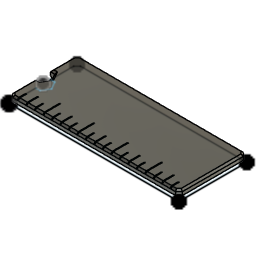
Magnetic Stud Finer v1 (Autodesk Fusion 360 design; units mm, degrees)
Autodesk Fusion 360 part; units mm, degrees
sketch "Sketch1" plane through (0, 0, 0) normal (0, 0, 1) x (1, 0, 0)
  line L0 (2.54, 0) -> (124.46, 0)
  line L1 (127, 2.54) -> (127, 48.26)
  line L2 (124.46, 50.8) -> (2.54, 50.8)
  line L3 (0, 48.26) -> (2.54, 50.8)
  line L4 (0, 2.54) -> (2.54, 0)
  line L5 (124.46, 50.8) -> (127, 48.26)
  line L6 (127, 2.54) -> (124.46, 0)
  line L7 (6.35, 25.4) -> (3.175, 30.8993)
  line L8 (3.175, 30.8993) -> (0, 30.8993)
  line L9 (0, 19.9007) -> (3.175, 19.9007)
  line L10 (3.175, 19.9007) -> (6.35, 25.4)
  line L11 (0, 48.26) -> (0, 30.8993)
  line L12 (0, 19.9007) -> (0, 2.54)
  point P0 (0.0687, -0.0333)
  point P1 (127, 0)
  point P2 (127, 50.8)
  point P3 (0, 50.8)
  point P4 (0, 25.4)
  dimension "d19" = 50.8
  dimension "d20" = 127
  dimension "d21" = 2.54
  dimension "d22" = 2.54
  dimension "d23" = 2.54
  dimension "d24" = 2.54
  dimension "d25" = 2.54
  dimension "d26" = 2.54
  dimension "d27" = 2.54
  dimension "d28" = 2.54
  dimension "d29" = 6.35
  constraint horizontal L0
  constraint vertical L1
  constraint horizontal L2
  constraint vertical L11
  constraint coincident P3 L11
  constraint coincident P3 L2
  constraint coincident origin L11
  constraint coincident origin L0
  constraint coincident P2 L2
  constraint coincident P2 L1
  constraint coincident P1 L1
  constraint coincident P1 L0
  constraint coincident L9.start L11
  constraint collinear L11 L12
  constraint coincident P4 L11
  measures "d19" distance of L0 L2
  measures "d20" distance of L1 L11
  measures "d21" distance of P3 L3.start
  measures "d22" distance of P3 L2.end
  measures "d23" distance of origin L4.start
  measures "d24" distance of origin L0.start
  measures "d25" distance of P2 L2.start
  measures "d26" distance of P2 L1.end
  measures "d27" distance of P1 L1.start
  measures "d28" distance of P1 L0.end
  measures "d29" distance of L7.start P4
extrude "Extrude2" add sketch "Sketch1" along normal blind 6.35
chamfer "Chamfer3" distance 2.54 angle 45 1 faces at (85.09, 25.4, 0)
chamfer "Chamfer4" distance 1.27 angle 45 1 faces at (85.09, 25.4, 6.35)
delete_face "DeleteFace11" 4 faces at (1.905, 31.7459, 1.6933) (6.7581, 28.0798, 0.8467) (6.7581, 22.7202, 0.8467) (1.905, 19.0541, 1.6933)
sketch "Sketch2" plane through (0, 0, 6.35) normal (0, 0, 1) x (-1, 0, 0)
  line L0 (-125.73, -47.7339) -> (-123.9339, -49.53)
  line L1 (-123.9339, -49.53) -> (-3.0661, -49.53)
  line L2 (-3.0661, -49.53) -> (-1.27, -47.7339)
  line L3 (-1.27, -47.7339) -> (-1.27, -32.1693)
  line L4 (-1.27, -32.1693) -> (-3.9082, -32.1693)
  line L5 (-3.9082, -32.1693) -> (-7.8165, -25.4)
  line L6 (-7.8165, -25.4) -> (-3.9082, -18.6307)
  line L7 (-3.9082, -18.6307) -> (-1.27, -18.6307)
  line L8 (-1.27, -18.6307) -> (-1.27, -3.0661)
  line L9 (-1.27, -3.0661) -> (-3.0661, -1.27)
  line L10 (-3.0661, -1.27) -> (-123.9339, -1.27)
  line L11 (-123.9339, -1.27) -> (-125.73, -3.0661)
  line L12 (-125.73, -3.0661) -> (-125.73, -47.7339)
  line L13 (0, -19.9007) -> (0, -2.54)
  line L14 (-25.4, 0) -> (-25.4, -12.7)
  line L15 (-50.8, 0) -> (-50.8, -12.7)
  line L16 (-76.2, 0) -> (-76.2, -12.7)
  line L17 (-101.6, 0) -> (-101.6, -12.7)
  line L18 (-25.7175, 0) -> (-25.0825, 0)
  line L19 (-25.0825, 0) -> (-25.0825, -12.7)
  line L20 (-25.0825, -12.7) -> (-25.7175, -12.7)
  line L21 (-25.7175, -12.7) -> (-25.7175, 0)
  line L22 (-25.7175, 0) -> (-25.0825, -12.7) construction
  line L23 (-25.0825, 0) -> (-25.7175, -12.7) construction
  line L24 (-51.1175, 0) -> (-50.4825, 0)
  line L25 (-50.4825, 0) -> (-50.4825, -12.7)
  line L26 (-50.4825, -12.7) -> (-51.1175, -12.7)
  line L27 (-51.1175, -12.7) -> (-51.1175, 0)
  line L28 (-51.1175, 0) -> (-50.4825, -12.7) construction
  line L29 (-50.4825, 0) -> (-51.1175, -12.7) construction
  line L30 (-76.5175, 0) -> (-75.8825, 0)
  line L31 (-75.8825, 0) -> (-75.8825, -12.7)
  line L32 (-75.8825, -12.7) -> (-76.5175, -12.7)
  line L33 (-76.5175, -12.7) -> (-76.5175, 0)
  line L34 (-76.5175, 0) -> (-75.8825, -12.7) construction
  line L35 (-75.8825, 0) -> (-76.5175, -12.7) construction
  line L36 (-101.9175, 0) -> (-101.2825, 0)
  line L37 (-101.2825, 0) -> (-101.2825, -12.7)
  line L38 (-101.2825, -12.7) -> (-101.9175, -12.7)
  line L39 (-101.9175, -12.7) -> (-101.9175, 0)
  line L40 (-101.9175, 0) -> (-101.2825, -12.7) construction
  line L41 (-101.2825, 0) -> (-101.9175, -12.7) construction
  line L42 (-12.7, 0) -> (-12.7, -8.89)
  line L43 (-38.1, 0) -> (-38.1, -8.89)
  line L44 (-63.5, 0) -> (-63.5, -8.89)
  line L45 (-88.9, 0) -> (-88.9, -8.89)
  line L46 (-114.3, 0) -> (-114.3, -8.89)
  line L47 (-6.35, 0) -> (-6.35, -6.35)
  line L48 (-19.05, 0) -> (-19.05, -6.35)
  line L49 (-31.75, 0) -> (-31.75, -6.35)
  line L50 (-44.45, 0) -> (-44.45, -6.35)
  line L51 (-57.15, 0) -> (-57.15, -6.35)
  line L52 (-69.85, 0) -> (-69.85, -6.35)
  line L53 (-82.55, 0) -> (-82.55, -6.35)
  line L54 (-95.25, 0) -> (-95.25, -6.35)
  line L55 (-107.95, 0) -> (-107.95, -6.35)
  line L56 (-120.65, 0) -> (-120.65, -6.35)
  line L57 (-6.6675, 0) -> (-6.0325, 0)
  line L58 (-6.0325, 0) -> (-6.0325, -6.35)
  line L59 (-6.0325, -6.35) -> (-6.6675, -6.35)
  line L60 (-6.6675, -6.35) -> (-6.6675, 0)
  line L61 (-6.6675, 0) -> (-6.0325, -6.35) construction
  line L62 (-6.0325, 0) -> (-6.6675, -6.35) construction
  line L63 (-13.0175, 0) -> (-12.3825, 0)
  line L64 (-12.3825, 0) -> (-12.3825, -8.89)
  line L65 (-12.3825, -8.89) -> (-13.0175, -8.89)
  line L66 (-13.0175, -8.89) -> (-13.0175, 0)
  line L67 (-13.0175, 0) -> (-12.3825, -8.89) construction
  line L68 (-12.3825, 0) -> (-13.0175, -8.89) construction
  line L69 (-19.3675, 0) -> (-18.7325, 0)
  line L70 (-18.7325, 0) -> (-18.7325, -6.35)
  line L71 (-18.7325, -6.35) -> (-19.3675, -6.35)
  line L72 (-19.3675, -6.35) -> (-19.3675, 0)
  line L73 (-19.3675, 0) -> (-18.7325, -6.35) construction
  line L74 (-18.7325, 0) -> (-19.3675, -6.35) construction
  line L75 (-32.0675, 0) -> (-31.4325, 0)
  line L76 (-31.4325, 0) -> (-31.4325, -6.35)
  line L77 (-31.4325, -6.35) -> (-32.0675, -6.35)
  line L78 (-32.0675, -6.35) -> (-32.0675, 0)
  line L79 (-32.0675, 0) -> (-31.4325, -6.35) construction
  line L80 (-31.4325, 0) -> (-32.0675, -6.35) construction
  line L81 (-38.4175, 0) -> (-37.7825, 0)
  line L82 (-37.7825, 0) -> (-37.7825, -8.89)
  line L83 (-37.7825, -8.89) -> (-38.4175, -8.89)
  line L84 (-38.4175, -8.89) -> (-38.4175, 0)
  line L85 (-38.4175, 0) -> (-37.7825, -8.89) construction
  line L86 (-37.7825, 0) -> (-38.4175, -8.89) construction
  line L87 (-44.7675, 0) -> (-44.1325, 0)
  line L88 (-44.1325, 0) -> (-44.1325, -6.35)
  line L89 (-44.1325, -6.35) -> (-44.7675, -6.35)
  line L90 (-44.7675, -6.35) -> (-44.7675, 0)
  line L91 (-44.7675, 0) -> (-44.1325, -6.35) construction
  line L92 (-44.1325, 0) -> (-44.7675, -6.35) construction
  line L93 (-57.4675, 0) -> (-56.8325, 0)
  line L94 (-56.8325, 0) -> (-56.8325, -6.35)
  line L95 (-56.8325, -6.35) -> (-57.4675, -6.35)
  line L96 (-57.4675, -6.35) -> (-57.4675, 0)
  line L97 (-57.4675, 0) -> (-56.8325, -6.35) construction
  line L98 (-56.8325, 0) -> (-57.4675, -6.35) construction
  line L99 (-63.8175, 0) -> (-63.1825, 0)
  line L100 (-63.1825, 0) -> (-63.1825, -8.89)
  line L101 (-63.1825, -8.89) -> (-63.8175, -8.89)
  line L102 (-63.8175, -8.89) -> (-63.8175, 0)
  line L103 (-63.8175, 0) -> (-63.1825, -8.89) construction
  line L104 (-63.1825, 0) -> (-63.8175, -8.89) construction
  line L105 (-70.1675, 0) -> (-69.5325, 0)
  line L106 (-69.5325, 0) -> (-69.5325, -6.35)
  line L107 (-69.5325, -6.35) -> (-70.1675, -6.35)
  line L108 (-70.1675, -6.35) -> (-70.1675, 0)
  line L109 (-70.1675, 0) -> (-69.5325, -6.35) construction
  line L110 (-69.5325, 0) -> (-70.1675, -6.35) construction
  line L111 (-82.8675, 0) -> (-82.2325, 0)
  line L112 (-82.2325, 0) -> (-82.2325, -6.35)
  line L113 (-82.2325, -6.35) -> (-82.8675, -6.35)
  line L114 (-82.8675, -6.35) -> (-82.8675, 0)
  line L115 (-82.8675, 0) -> (-82.2325, -6.35) construction
  line L116 (-82.2325, 0) -> (-82.8675, -6.35) construction
  line L117 (-89.2175, 0) -> (-88.5825, 0)
  line L118 (-88.5825, 0) -> (-88.5825, -8.89)
  line L119 (-88.5825, -8.89) -> (-89.2175, -8.89)
  line L120 (-89.2175, -8.89) -> (-89.2175, 0)
  line L121 (-89.2175, 0) -> (-88.5825, -8.89) construction
  line L122 (-88.5825, 0) -> (-89.2175, -8.89) construction
  line L123 (-95.5675, 0) -> (-94.9325, 0)
  line L124 (-94.9325, 0) -> (-94.9325, -6.35)
  line L125 (-94.9325, -6.35) -> (-95.5675, -6.35)
  line L126 (-95.5675, -6.35) -> (-95.5675, 0)
  line L127 (-95.5675, 0) -> (-94.9325, -6.35) construction
  line L128 (-94.9325, 0) -> (-95.5675, -6.35) construction
  line L129 (-108.2675, 0) -> (-107.6325, 0)
  line L130 (-107.6325, 0) -> (-107.6325, -6.35)
  line L131 (-107.6325, -6.35) -> (-108.2675, -6.35)
  line L132 (-108.2675, -6.35) -> (-108.2675, 0)
  line L133 (-108.2675, 0) -> (-107.6325, -6.35) construction
  line L134 (-107.6325, 0) -> (-108.2675, -6.35) construction
  line L135 (-114.6175, 0) -> (-113.9825, 0)
  line L136 (-113.9825, 0) -> (-113.9825, -8.89)
  line L137 (-113.9825, -8.89) -> (-114.6175, -8.89)
  line L138 (-114.6175, -8.89) -> (-114.6175, 0)
  line L139 (-114.6175, 0) -> (-113.9825, -8.89) construction
  line L140 (-113.9825, 0) -> (-114.6175, -8.89) construction
  line L141 (-120.9675, 0) -> (-120.3325, 0)
  line L142 (-120.3325, 0) -> (-120.3325, -6.35)
  line L143 (-120.3325, -6.35) -> (-120.9675, -6.35)
  line L144 (-120.9675, -6.35) -> (-120.9675, 0)
  line L145 (-120.9675, 0) -> (-120.3325, -6.35) construction
  line L146 (-120.3325, 0) -> (-120.9675, -6.35) construction
  arc A0 (-127, 0) -> (0, 0) centre (-63.5, 66.675) ccw
  point P0 (-25.4, -6.35)
  point P1 (-50.8, -6.35)
  point P2 (-76.2, -6.35)
  point P3 (-101.6, -6.35)
  point P4 (-6.35, -3.175)
  point P5 (-12.7, -4.445)
  point P6 (-19.05, -3.175)
  point P7 (-31.75, -3.175)
  point P8 (-38.1, -4.445)
  point P9 (-44.45, -3.175)
  point P10 (-57.15, -3.175)
  point P11 (-63.5, -4.445)
  point P12 (-69.85, -3.175)
  point P13 (-82.55, -3.175)
  point P14 (-88.9, -4.445)
  point P15 (-95.25, -3.175)
  point P16 (-107.95, -3.175)
  point P17 (-114.3, -4.445)
  point P18 (-120.65, -3.175)
  dimension "d43" = 12.7
  dimension "d44" = 12.7
  dimension "d45" = 25.4
  dimension "d46" = 12.7
  dimension "d47" = 25.4
  dimension "d48" = 25.4
  dimension "d49" = 0.635
  dimension "d50" = 0.635
  dimension "d51" = 0.635
  dimension "d52" = 0.635
  dimension "d55" = 8.89
  dimension "d56" = 8.89
  dimension "d57" = 25.4
  dimension "d58" = 8.89
  dimension "d59" = 25.4
  dimension "d60" = 8.89
  dimension "d61" = 25.4
  dimension "d62" = 8.89
  dimension "d63" = 25.4
  dimension "d64" = 6.35
  dimension "d65" = 12.7
  dimension "d66" = 6.35
  dimension "d67" = 6.35
  dimension "d68" = 6.35
  dimension "d69" = 6.35
  dimension "d70" = 6.35
  dimension "d71" = 6.35
  dimension "d72" = 6.35
  dimension "d73" = 6.35
  dimension "d74" = 6.35
  dimension "d75" = 6.35
  dimension "d76" = 6.35
  dimension "d77" = 12.7
  dimension "d79" = 0.635
  dimension "d80" = 0.635
  dimension "d81" = 0.635
  dimension "d82" = 0.635
  dimension "d83" = 0.635
  dimension "d84" = 0.635
  dimension "d85" = 0.635
  dimension "d86" = 0.635
  dimension "d87" = 0.635
  dimension "d88" = 0.635
  dimension "d89" = 0.635
  dimension "d90" = 0.635
  dimension "d91" = 0.635
  dimension "d92" = 0.635
  dimension "d93" = 0.635
  dimension "d96" = 10.0076
  constraint horizontal L18
  constraint perpendicular L18 L19
  constraint parallel L18 L20
  constraint parallel L19 L21
  constraint coincident L22 P0
  constraint coincident L23 P0
  constraint midpoint L14 P0
  constraint horizontal L24
  constraint perpendicular L24 L25
  constraint parallel L24 L26
  constraint parallel L25 L27
  constraint coincident L28 P1
  constraint coincident L29 P1
  constraint midpoint L15 P1
  constraint horizontal L30
  constraint perpendicular L30 L31
  constraint parallel L30 L32
  constraint parallel L31 L33
  constraint coincident L34 P2
  constraint coincident L35 P2
  constraint midpoint L16 P2
  constraint horizontal L36
  constraint perpendicular L36 L37
  constraint parallel L36 L38
  constraint parallel L37 L39
  constraint coincident L40 P3
  constraint coincident L41 P3
  constraint midpoint L17 P3
  constraint perpendicular L10 L42
  constraint perpendicular L10 L44
  constraint perpendicular L10 L46
  constraint perpendicular L10 L48
  constraint perpendicular L10 L50
  constraint perpendicular L10 L53
  constraint perpendicular L10 L54
  constraint perpendicular L10 L55
  constraint horizontal L57
  constraint perpendicular L57 L58
  constraint parallel L57 L59
  constraint parallel L58 L60
  constraint coincident L61 P4
  constraint coincident L62 P4
  constraint midpoint L47 P4
  constraint horizontal L63
  constraint perpendicular L63 L64
  constraint parallel L63 L65
  constraint parallel L64 L66
  constraint coincident L67 P5
  constraint coincident L68 P5
  constraint midpoint L42 P5
  constraint horizontal L69
  constraint perpendicular L69 L70
  constraint parallel L69 L71
  constraint parallel L70 L72
  constraint coincident L73 P6
  constraint coincident L74 P6
  constraint midpoint L48 P6
  constraint horizontal L75
  constraint perpendicular L75 L76
  constraint parallel L75 L77
  constraint parallel L76 L78
  constraint coincident L79 P7
  constraint coincident L80 P7
  constraint midpoint L49 P7
  constraint horizontal L81
  constraint perpendicular L81 L82
  constraint parallel L81 L83
  constraint parallel L82 L84
  constraint coincident L85 P8
  constraint coincident L86 P8
  constraint midpoint L43 P8
  constraint horizontal L87
  constraint perpendicular L87 L88
  constraint parallel L87 L89
  constraint parallel L88 L90
  constraint coincident L91 P9
  constraint coincident L92 P9
  constraint midpoint L50 P9
  constraint horizontal L93
  constraint perpendicular L93 L94
  constraint parallel L93 L95
  constraint parallel L94 L96
  constraint coincident L97 P10
  constraint coincident L98 P10
  constraint midpoint L51 P10
  constraint horizontal L99
  constraint perpendicular L99 L100
  constraint parallel L99 L101
  constraint parallel L100 L102
  constraint coincident L103 P11
  constraint coincident L104 P11
  constraint midpoint L44 P11
  constraint horizontal L105
  constraint perpendicular L105 L106
  constraint parallel L105 L107
  constraint parallel L106 L108
  constraint coincident L109 P12
  constraint coincident L110 P12
  constraint midpoint L52 P12
  constraint horizontal L111
  constraint perpendicular L111 L112
  constraint parallel L111 L113
  constraint parallel L112 L114
  constraint coincident L115 P13
  constraint coincident L116 P13
  constraint midpoint L53 P13
  constraint horizontal L117
  constraint perpendicular L117 L118
  constraint parallel L117 L119
  constraint parallel L118 L120
  constraint coincident L121 P14
  constraint coincident L122 P14
  constraint midpoint L45 P14
  constraint horizontal L123
  constraint perpendicular L123 L124
  constraint parallel L123 L125
  constraint parallel L124 L126
  constraint coincident L127 P15
  constraint coincident L128 P15
  constraint midpoint L54 P15
  constraint horizontal L129
  constraint perpendicular L129 L130
  constraint parallel L129 L131
  constraint parallel L130 L132
  constraint coincident L133 P16
  constraint coincident L134 P16
  constraint midpoint L55 P16
  constraint horizontal L135
  constraint perpendicular L135 L136
  constraint parallel L135 L137
  constraint parallel L136 L138
  constraint coincident L139 P17
  constraint coincident L140 P17
  constraint midpoint L46 P17
  constraint horizontal L141
  constraint perpendicular L141 L142
  constraint parallel L141 L143
  constraint parallel L142 L144
  constraint coincident L145 P18
  constraint coincident L146 P18
  constraint midpoint L56 P18
  constraint coincident A0.end origin
  measures "d43" distance of L14.start L14.end
  measures "d44" distance of L15.start L15.end
  measures "d45" distance of L14 L15
  measures "d46" distance of L16.start L16.end
  measures "d47" distance of L15 L16
  measures "d48" distance of L16 L17
  measures "d49" distance of L19.end L20.end
  measures "d50" distance of L25.end L26.end
  measures "d51" distance of L31.end L32.end
  measures "d52" distance of L37.end L38.end
  measures "d55" distance of L42.start L42.end
  measures "d56" distance of L43.start L43.end
  measures "d57" distance of L42 L43
  measures "d58" distance of L44.start L44.end
  measures "d59" distance of L43 L44
  measures "d60" distance of L45.start L45.end
  measures "d61" distance of L44 L45
  measures "d62" distance of L46.start L46.end
  measures "d63" distance of L45 L46
  measures "d64" distance of L48.start L48.end
  measures "d65" distance of L47 L48
  measures "d66" distance of L49.start L49.end
  measures "d67" distance of L43 L49
  measures "d68" distance of L50.start L50.end
  measures "d69" distance of L51.start L51.end
  measures "d70" distance of L52.start L52.end
  measures "d71" distance of L53.start L53.end
  measures "d72" distance of L16 L53
  measures "d73" distance of L54.start L54.end
  measures "d74" distance of L45 L54
  measures "d75" distance of L55.start L55.end
  measures "d76" distance of L56.start L56.end
  measures "d77" distance of L55 L56
  measures "d79" distance of L58.end L59.end
  measures "d80" distance of L64.end L65.end
  measures "d81" distance of L70.end L71.end
  measures "d82" distance of L76.end L77.end
  measures "d83" distance of L82.end L83.end
  measures "d84" distance of L88.end L89.end
  measures "d85" distance of L94.end L95.end
  measures "d86" distance of L100.end L101.end
  measures "d87" distance of L106.end L107.end
  measures "d88" distance of L112.end L113.end
  measures "d89" distance of L118.end L119.end
  measures "d90" distance of L124.end L125.end
  measures "d91" distance of L130.end L131.end
  measures "d92" distance of L136.end L137.end
  measures "d93" distance of L142.end L143.end
extrude "Extrude3" cut sketch "Sketch2" against normal blind 1.27 contours L10 L17 L36 L39 | L10 L17 L38 L39 | L10 L17 L36 L37 | L10 L17 L37 L38 | L10 L14 L19 L20 | L10 L14 L18 L19 | L10 L14 L20 L21 | L10 L14 L18 L21 | L10 L16 L30 L33 | L10 L16 L32 L33 | L10 L16 L30 L31 | L10 L16 L31 L32 | L10 L15 L25 L26 | L10 L15 L24 L25 | L10 L15 L26 L27 | L10 L15 L24 L27
extrude "Extrude4" cut sketch "Sketch2" against normal blind 1.27 contours L56 L143 L144 A0 | L10 L56 L144 A0 | L10 L56 L141 L144 | L56 L142 L143 A0 | L10 L56 L142 A0 | L10 L56 L141 L142 | L47 L59 L60 A0 | L10 L47 L60 A0 | L10 L46 L135 L138 | L10 L46 L137 L138 | L10 L47 L57 L60 | L47 L58 L59 A0 | L10 L47 L58 A0 | L10 L46 L135 L136 | L10 L46 L136 L137 | L10 L47 L57 L58 | L10 L42 L64 L65 | L10 L42 L63 L64 | L10 L42 L65 L66 | L10 L42 L63 L66 | L10 L55 L129 L132 | L10 L55 L131 L132 | L10 L55 L129 L130 | L10 L55 L130 L131 | L10 L48 L70 L71 | L10 L48 L69 L70 | L10 L48 L71 L72 | L10 L48 L69 L72 | L10 L54 L123 L126 | L10 L54 L125 L126 | L10 L54 L123 L124 | L10 L54 L124 L125 | L10 L49 L76 L77 | L10 L49 L75 L76 | L10 L49 L77 L78 | L10 L49 L75 L78 | L10 L45 L117 L120 | L10 L45 L119 L120 | L10 L45 L117 L118 | L10 L45 L118 L119 | L10 L43 L82 L83 | L10 L43 L81 L82 | L10 L43 L83 L84 | L10 L43 L81 L84 | L10 L53 L111 L114 | L10 L53 L113 L114 | L10 L53 L111 L112 | L10 L53 L112 L113 | L10 L50 L88 L89 | L10 L50 L87 L88 | L10 L50 L89 L90 | L10 L50 L87 L90 | L10 L52 L105 L108 | L10 L52 L107 L108 | L10 L52 L105 L106 | L10 L52 L106 L107 | L10 L51 L94 L95 | L10 L51 L93 L94 | L10 L51 L95 L96 | L10 L51 L93 L96 | L10 L44 L99 L102 | L10 L44 L101 L102 | L10 L44 L99 L100 | L10 L44 L100 L101
equation "d22 = d21"
equation "d24 = d23"
equation "d26 = d25"
equation "d28 = d27"
